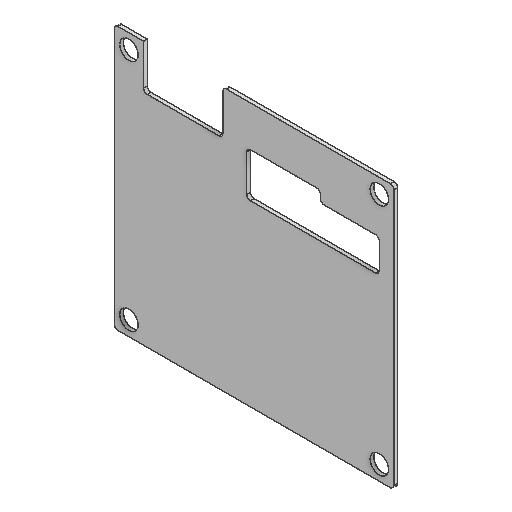
# Autodesk Inventor part: cosmic-ray-detector-v2-enclosure-fdm-body
Saved by Autodesk Inventor 2025.2 (Build 292293000, 293)
## iProperties
Created: 2026-02-25
Part Number: cosmic-ray-detector-v2-enclosure-fdm-body
Material: Generic
Document SubType Name: Modeling
Designer: kaduo
Density: 1 g/cm^3
Appearance: Default
Author: kaduo
Autodesk Inventor part; units mm, degrees
ref_plane "YZ Plane" through (0, 0, 0) normal (1, 0, 0) x (0, 1, 0)
ref_plane "XZ Plane" through (0, 0, 0) normal (0, 1, 0) x (-1, 0, 0)
ref_plane "XY Plane" through (0, 0, 0) normal (0, 0, 1) x (1, 0, 0)
sketch "Sketch1" plane through (0, 0, 0) normal (0, 0, 1) x (1, 0, 0)
  line L0 (0, 0) -> (-76, 0)
  line L1 (-76, 0) -> (-76, -71.5)
  line L2 (-76, -71.5) -> (0, -71.5)
  line L3 (0, -71.5) -> (0, 0)
  dimension "d122" = 76
  dimension "d123" = 71.5
  constraints: 8 end point, 2 parallel, 1 horizontal, 1 perpendicular
  measures "d122" distance of L2.end L1.end
  measures "d123" distance of L1.end L0.end
extrude "Extrusion1" add sketch "Sketch1" along normal blind 1
sketch "Sketch13" plane through (0, 0, 0) normal (0, 0, -1) x (-1, 0, 0)
  line L0 (0, -71.5) -> (0, 0) projected
  line L1 (0, 0) -> (76, 0) projected
  line L2 (76, -71.5) -> (0, -71.5) projected
  line L3 (76, 0) -> (76, -71.5) projected
  point P0 (4, -4)
  point P1 (4, -67.5)
  point P2 (72, -4)
  point P3 (72, -67.5)
  dimension "d124" = 4
  dimension "d125" = 4
  dimension "d126" = 4
  dimension "d127" = 4
  dimension "d128" = 4
  dimension "d129" = 4
  dimension "d130" = 4
  dimension "d131" = 4
  measures "d124" distance from line of L0 point (4, -4)
  measures "d125" distance from line of L1 point (4, -4)
  measures "d126" distance from line of L2 point (4, -67.5)
  measures "d127" distance from line of L0 point (4, -67.5)
  measures "d128" distance from line of L2 point (72, -67.5)
  measures "d129" distance from line of L3 point (72, -67.5)
  measures "d130" distance from line of L3 point (72, -4)
  measures "d131" distance from line of L1 point (72, -4)
hole "Hole4" at (-72, -4, 0) at (-72, -67.5, 0) at (-4, -4, 0) at (-4, -67.5, 0) direction (0, 0, 1) diameter 5 depth 1
sketch "Sketch14" plane through (0, 0, 0) normal (0, 0, -1) x (-1, 0, 0)
  line L0 (20, -11) -> (40, -11)
  line L1 (40, -11) -> (40, -23)
  line L2 (40, -23) -> (20, -23)
  line L3 (20, -23) -> (20, -11)
  line L4 (0, -71.5) -> (0, 0) projected
  line L5 (0, 0) -> (76, 0) projected
  line L6 (4, -14) -> (20, -14)
  line L7 (20, -14) -> (20, -23)
  line L8 (20, -23) -> (4, -23)
  line L9 (4, -23) -> (4, -14)
  line L10 (46.5, 0) -> (68, 0)
  line L11 (68, 0) -> (68, -12)
  line L12 (68, -12) -> (46.5, -12)
  line L13 (46.5, -12) -> (46.5, 0)
  line L14 (76, 0) -> (76, -71.5) projected
  point P0 (68, 0)
  dimension "d143" = 20
  dimension "d144" = 12
  dimension "d145" = 20
  dimension "d146" = 11
  dimension "d148" = 14
  dimension "d149" = 9
  dimension "d150" = 16
  dimension "d153" = 21.5
  dimension "d154" = 12
  dimension "d155" = 8
  constraints: 24 end point, 6 parallel, 3 horizontal, 3 perpendicular, 1 point on line
  measures "d143" distance of L1.end L2.end
  measures "d144" distance of L0.end L1.end
  measures "d145" distance between parallel lines of L4 L3
  measures "d146" distance between parallel lines of L5 L0
  measures "d148" distance between parallel lines of L5 L6
  measures "d149" distance of L6.end L7.end
  measures "d150" distance of L7.end L8.end
  measures "d153" distance of L11.end L12.end
  measures "d154" distance of L10.end L11.end
  measures "d155" distance between parallel lines of L14 L11
extrude "Extrusion10" cut sketch "Sketch14" against normal blind 1.5
fillet "Fillet1" radius 1 13 edges at (0, 0, 0.5) (0, -71.5, 0.5) (-68, -12, 0.5) (-76, 0, 0.5) (-46.5, 0, 0.5) (-46.5, -12, 0.5) (-76, -71.5, 0.5) (-4, -23, 0.5) (-40, -23, 0.5) (-20, -14, 0.5) (-20, -11, 0.5) (-4, -14, 0.5) (-40, -11, 0.5)
body "Solid1"
